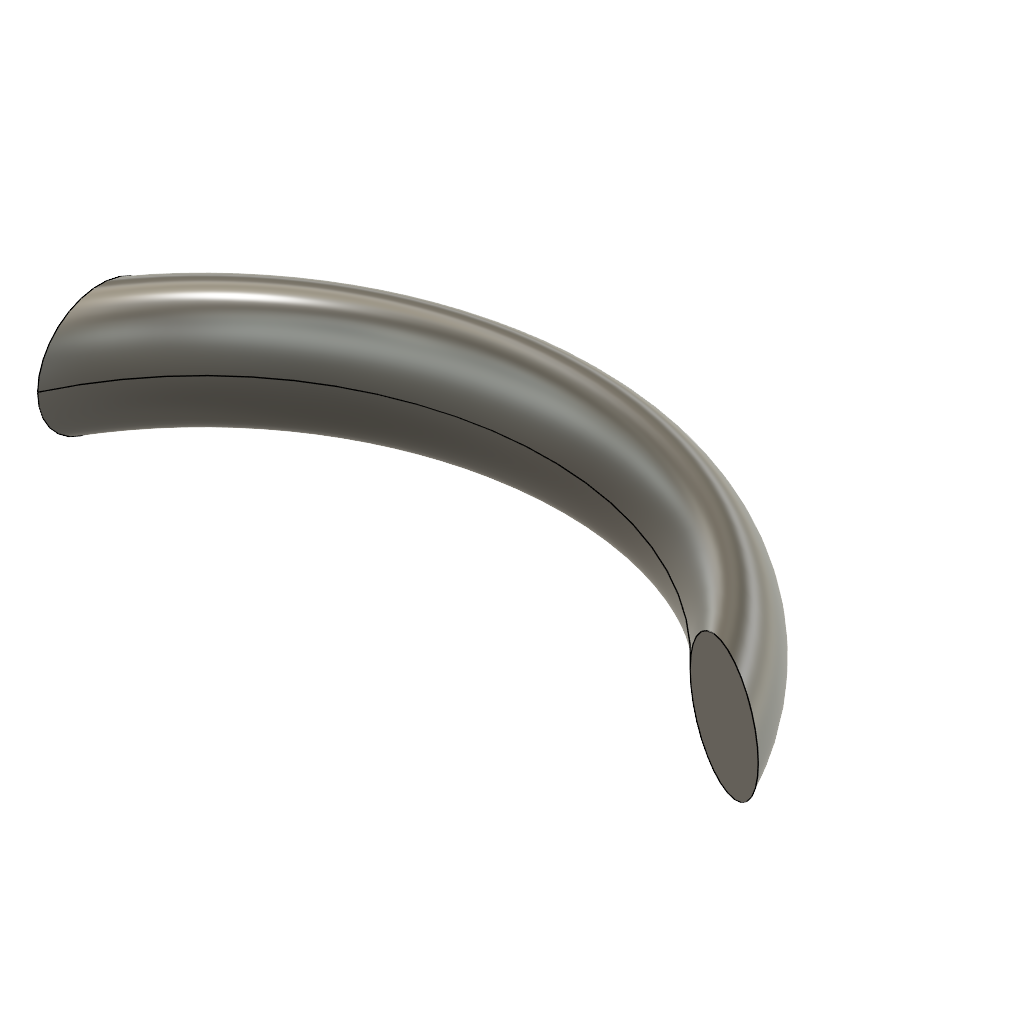
sweep_arc_path (Autodesk Fusion 360 design; units mm, degrees)
part number: 2026-11-13-14-38-35-971
Autodesk Fusion 360 part; units mm, degrees
sketch "Sketch1" plane through (0, 0, 0) normal (1, 0, 0) x (0, 0, -1)
  circle A0 centre (0, 0) radius 3
sketch "Sketch2" plane through (0, 0, 0) normal (0, 1, 0) x (1, 0, 0)
  arc A0 (30, 0) -> (0, 0) centre (15, -10.0625) ccw
sweep "Sweep1" add profiles "Sketch1" path "Sketch2" along A0 section 1
